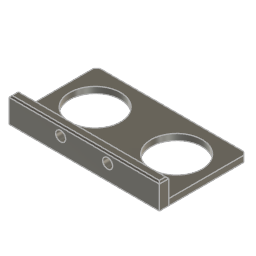
Ultrasonic-Sensor-Bracket-Horizontal (Autodesk Fusion 360 design; units mm, degrees)
part number: 2026-04-13-16-50-10-778
Autodesk Fusion 360 part; units mm, degrees
sketch "Sketch1" plane through (0, 0, 0) normal (0, 0, 1) x (1, 0, 0)
  line L0 (24, 11.5) -> (-24, 11.5)
  line L1 (-24, 11.5) -> (-24, -13.5)
  line L2 (-24, -13.5) -> (24, -13.5)
  line L3 (24, -13.5) -> (24, 11.5)
  circle A0 centre (-13, 0) radius 8.125
  circle A1 centre (13, 0) radius 8.125
  line L4 (-24, -13.5) -> (24, -13.5)
  line L5 (24, -13.5) -> (24, -16.5)
  line L6 (24, -16.5) -> (-24, -16.5)
  line L7 (-24, -16.5) -> (-24, -13.5)
  dimension "d3" = 16.25
  dimension "d4" = 16.25
  constraint horizontal L0
  constraint perpendicular L0 L1
  constraint parallel L0 L2
  constraint parallel L1 L3
  constraint horizontal L4
  constraint vertical L5
  constraint horizontal L6
  constraint vertical L7
  measures "d3" diameter of A0
  measures "d4" diameter of A1
extrude "Extrude1" add sketch "Sketch1" along normal blind 2 contours L0 L1 L2 L3 L4 makes body 1
extrude "Extrude2" add sketch "Sketch1" along normal blind 8 separate body contours L2 L4 L5 L6 L7 makes body 2
sketch "Sketch2" plane through (0, -13.5, 0) normal (0, 1, 0) x (-1, 0, 0)
  line L0 (-24, 0) -> (24, 0)
  line L1 (24, 0) -> (24, 8)
  line L2 (24, 8) -> (-24, 8)
  line L3 (-24, 8) -> (-24, 0)
  circle A0 centre (-7.5, 5) radius 1.6
  circle A1 centre (7.5, 5) radius 1.6
  circle A2 centre (7.5, 5) radius 1.6
extrude "Extrude3" cut sketch "Sketch2" against normal blind 3 contours A0 | A1 A2 bodies 2
sketch "Sketch3" plane through (-24, 0, 0) normal (-1, 0, 0) x (0, -1, 0)
  line L0 (13.5, 0) -> (16.5, 0)
  line L1 (16.5, 0) -> (16.5, 8)
  line L2 (16.5, 8) -> (13.5, 8)
  line L3 (13.5, 8) -> (13.5, 0)
chamfer "Chamfer1" distance 0.5 angle 45 4 edges at (0, -16.5, 8) (24, -15, 8) (-24, -15, 8) (0, -13.5, 8) on bodies 2
chamfer "Chamfer2" distance 1 angle 45 2 edges at (-24, 11.5, 1) (24, 11.5, 1) on bodies 1
